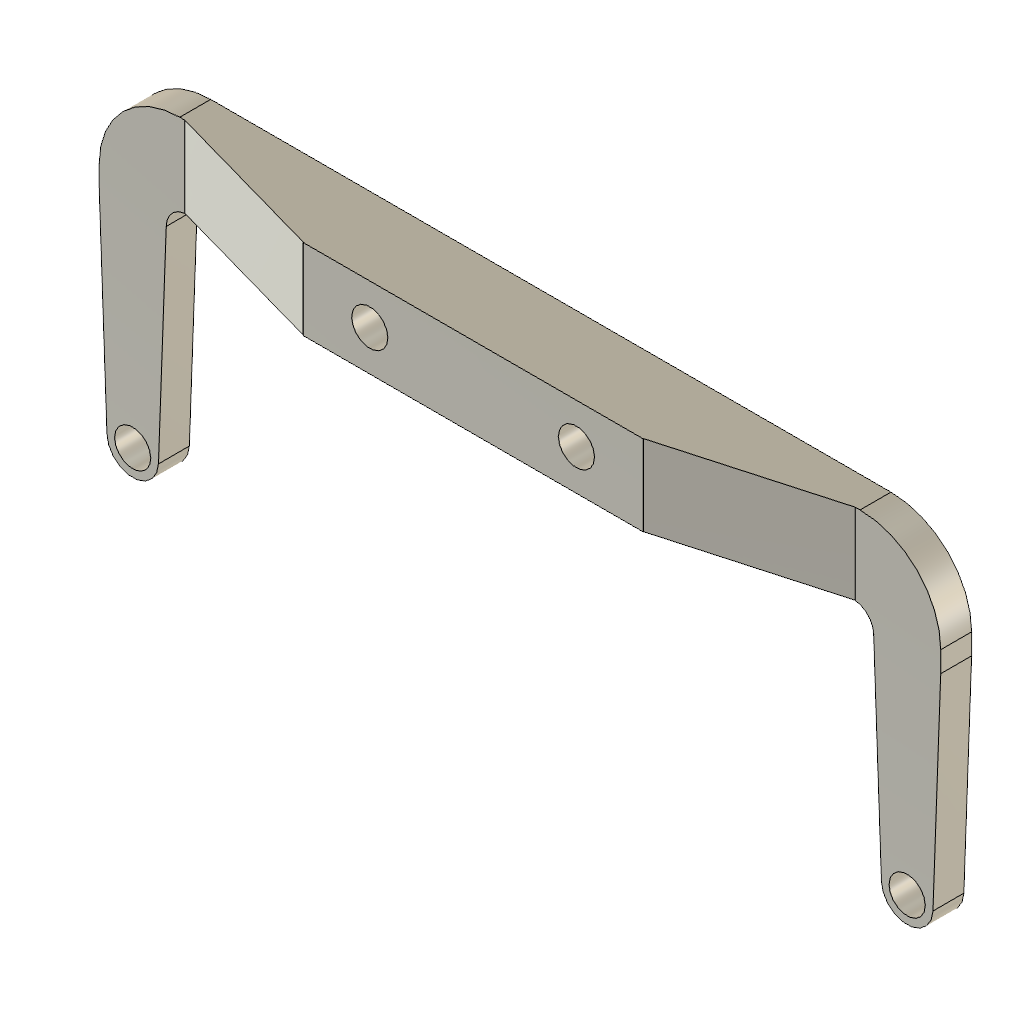
Eye Holder native (Autodesk Fusion 360 design; units mm, degrees)
part number: 2026-10-13-22-14-58-010
Autodesk Fusion 360 part; units mm, degrees
ref_plane "WorkPlane1" through (0, -1.2, 0) normal (0, 1, 0) x (0, 0, 1)
sketch "Plate" plane through (0, -1.2, 0) normal (0, 1, 0) x (1, 0, 0)
  line L0 (70.4366, -30.0122) -> (4.5629, -30.0122)
  arc A0 (-3.25, -22.1993) -> (4.5629, -30.0122) centre (4.5629, -22.1993) ccw
  line L1 (-3.25, -22.1993) -> (-3.25, -20.1993)
  line L2 (-3.25, -20.1993) -> (-2.4983, 0.0925)
  arc A1 (2.4983, 0.0925) -> (-2.4983, 0.0925) centre (0, 0) ccw
  line L3 (2.4983, 0.0925) -> (3.25, -20.1993)
  arc A2 (3.25, -20.1993) -> (5.2502, -22.1993) centre (5.2502, -20.1991) ccw
  line L4 (5.2502, -22.1993) -> (69.7495, -22.1993)
  arc A3 (69.7495, -22.1993) -> (71.7497, -20.2077) centre (69.7495, -20.1991) ccw
  line L5 (71.7497, -20.2077) -> (72.5017, 0.092)
  arc A4 (77.4983, 0.092) -> (72.5017, 0.092) centre (75, -0.0005) ccw
  line L6 (77.4983, 0.092) -> (78.2495, -20.187)
  line L7 (78.2495, -20.187) -> (78.2495, -22.1993)
  arc A5 (70.4366, -30.0122) -> (78.2495, -22.1993) centre (70.4366, -22.1993) ccw
  dimension "d33" = 7.8129
  dimension "d34" = 2.5
  dimension "d35" = 2.0002
  dimension "d36" = 4.5629
  dimension "d37" = 22.1993
  dimension "d38" = 5.2502
  dimension "d39" = 20.1991
  dimension "d40" = 69.7495
  dimension "d41" = 75
  dimension "d42" = 0.0005
  dimension "d43" = 70.4366
  dimension "d44" = 20.1993
  dimension "d45" = 2.4983
  dimension "d46" = 71.7497
  dimension "d47" = 77.4983
  constraint horizontal L0
  constraint vertical L1
  constraint horizontal L4
  constraint vertical L7
  constraint tangent L0 A5
  constraint tangent L0 A0
  constraint tangent A0 L1
  constraint tangent L2 A1
  constraint tangent A1 L3
  constraint tangent A2 L4
  constraint tangent L4 A3
  constraint tangent L5 A4
  constraint tangent A4 L6
  constraint tangent L7 A5
  constraint coincident A1.centre origin
  constraint equal A2 A3
  constraint equal A1 A4
  constraint equal A0 A5
  measures "d33" radius of A0
  measures "d34" radius of A1
  measures "d35" radius of A2
  measures "d36" horizontal distance of A1.centre A0.centre
  measures "d37" vertical distance of A1.centre A0.centre
  measures "d38" horizontal distance of A1.centre A2.centre
  measures "d39" vertical distance of A1.centre A2.centre
  measures "d40" horizontal distance of A1.centre A3.centre
  measures "d41" horizontal distance of A1.centre A4.centre
  measures "d42" vertical distance of A1.centre A4.centre
  measures "d43" horizontal distance of A1.centre A5.centre
  measures "d44" vertical distance of A1.centre L1.end
  measures "d45" horizontal distance of A1.centre A1.start
  measures "d46" horizontal distance of A1.centre A3.end
  measures "d47" horizontal distance of A1.centre A4.start
extrude "Plate (1)" add sketch "Plate" along normal mid plane 3
ref_plane "WorkPlane2" through (0, -4.7161, 0) normal (0, 1, 0) x (0, 0, 1)
sketch "Bar" plane through (0, -4.7161, 0) normal (0, 1, 0) x (1, 0, 0)
  arc A0 (5.0314, -22.1873) -> (5.2505, -22.1993) centre (5.2505, -20.1932) ccw
  line L0 (5.2505, -22.1993) -> (69.7496, -22.1993)
  arc A1 (69.7496, -22.1993) -> (69.9682, -22.1873) centre (69.7496, -20.2016) ccw
  line L1 (69.9682, -22.1873) -> (69.9682, -30.0122)
  line L2 (69.9682, -30.0122) -> (5.0314, -30.0122)
  line L3 (5.0314, -30.0122) -> (5.0314, -22.1873)
  dimension "d48" = 2.0061
  dimension "d49" = 1.9977
  dimension "d50" = 5.2505
  dimension "d51" = 20.1932
  dimension "d52" = 69.7496
  dimension "d53" = 5.0314
  dimension "d54" = 69.9682
  dimension "d55" = 30.0122
  constraint horizontal L0
  constraint vertical L1
  constraint horizontal L2
  constraint vertical L3
  constraint tangent A0 L0
  constraint tangent L0 A1
  measures "d48" radius of A0
  measures "d49" radius of A1
  measures "d50" horizontal distance of origin A0.centre
  measures "d51" vertical distance of origin A0.centre
  measures "d52" horizontal distance of origin A1.centre
  measures "d53" horizontal distance of origin A0.start
  measures "d54" horizontal distance of origin A1.end
  measures "d55" vertical distance of origin L1.end
extrude "Bar (1)" add sketch "Bar" along normal mid plane 5.0322
ref_plane "WorkPlane3" through (0, 0, 25.5061) normal (0, 0, 1) x (1, 0, 0)
sketch "Bar taper L" plane through (0, 0, 25.5061) normal (0, 0, 1) x (1, 0, 0)
  line L0 (5.0314, -2.7) -> (21.0314, -7.2)
  line L1 (21.0314, -7.2) -> (21.0314, -8.2322)
  line L2 (21.0314, -8.2322) -> (4, -8.2322)
  line L3 (4, -8.2322) -> (4, -2.7)
  line L4 (4, -2.7) -> (5.0314, -2.7)
  dimension "d56" = 5.0314
  dimension "d57" = 2.7
  dimension "d58" = 21.0314
  dimension "d59" = 7.2
  dimension "d60" = 8.2322
  dimension "d61" = 4
  constraint vertical L1
  constraint horizontal L2
  constraint vertical L3
  constraint horizontal L4
  measures "d56" horizontal distance of origin L0.start
  measures "d57" vertical distance of origin L0.start
  measures "d58" horizontal distance of origin L0.end
  measures "d59" vertical distance of origin L0.end
  measures "d60" vertical distance of origin L1.end
  measures "d61" horizontal distance of origin L2.end
extrude "Bar taper L (1)" cut sketch "Bar taper L" along normal mid plane 11.0122
ref_plane "WorkPlane4" through (0, 0, 25.5061) normal (0, 0, 1) x (1, 0, 0)
sketch "Bar taper R" plane through (0, 0, 25.5061) normal (0, 0, 1) x (1, 0, 0)
  line L0 (69.9682, -2.7) -> (71, -2.7)
  line L1 (71, -2.7) -> (71, -8.2322)
  line L2 (71, -8.2322) -> (53.9682, -8.2322)
  line L3 (53.9682, -8.2322) -> (53.9682, -7.2)
  line L4 (53.9682, -7.2) -> (69.9682, -2.7)
  dimension "d62" = 69.9682
  dimension "d63" = 2.7
  dimension "d64" = 71
  dimension "d65" = 8.2322
  dimension "d66" = 53.9682
  dimension "d67" = 7.2
  constraint horizontal L0
  constraint vertical L1
  constraint horizontal L2
  constraint vertical L3
  measures "d62" horizontal distance of origin L0.start
  measures "d63" vertical distance of origin L0.start
  measures "d64" horizontal distance of origin L0.end
  measures "d65" vertical distance of origin L1.end
  measures "d66" horizontal distance of origin L2.end
  measures "d67" vertical distance of origin L3.end
extrude "Bar taper R (1)" cut sketch "Bar taper R" along normal mid plane 11.0122
ref_plane "WorkPlane5" through (0, -3.4661, 0) normal (0, 1, 0) x (0, 0, 1)
sketch "Top hole L" plane through (0, -3.4661, 0) normal (0, 1, 0) x (1, 0, 0)
  circle A0 centre (27.4936, -26.1058) radius 1.75
  dimension "d68" = 3.5
  dimension "d69" = 27.4936
  dimension "d70" = 26.1058
  measures "d68" diameter of A0
  measures "d69" horizontal distance of origin A0.centre
  measures "d70" vertical distance of origin A0.centre
extrude "Top hole L (1)" cut sketch "Top hole L" along normal mid plane 7.5322
ref_plane "WorkPlane6" through (0, -3.4661, 0) normal (0, 1, 0) x (0, 0, 1)
sketch "Top hole R" plane through (0, -3.4661, 0) normal (0, 1, 0) x (1, 0, 0)
  circle A0 centre (47.5059, -26.1058) radius 1.75
  dimension "d71" = 3.5
  dimension "d72" = 47.5059
  dimension "d73" = 26.1058
  measures "d71" diameter of A0
  measures "d72" horizontal distance of origin A0.centre
  measures "d73" vertical distance of origin A0.centre
extrude "Top hole R (1)" cut sketch "Top hole R" along normal mid plane 7.5322
ref_plane "WorkPlane7" through (0, -1.2, 0) normal (0, 1, 0) x (0, 0, 1)
sketch "Pivot hole L" plane through (0, -1.2, 0) normal (0, 1, 0) x (1, 0, 0)
  circle A0 centre (0, 0) radius 1.75
  dimension "d74" = 3.5
  constraint coincident A0.centre origin
  measures "d74" diameter of A0
extrude "Pivot hole L (1)" cut sketch "Pivot hole L" along normal mid plane 3
ref_plane "WorkPlane8" through (0, -1.2, 0) normal (0, 1, 0) x (0, 0, 1)
sketch "Pivot hole R" plane through (0, -1.2, 0) normal (0, 1, 0) x (1, 0, 0)
  circle A0 centre (74.9995, 0) radius 1.75
  dimension "d75" = 3.5
  dimension "d76" = 74.9995
  constraint horizontal origin A0.centre
  measures "d75" diameter of A0
  measures "d76" horizontal distance of origin A0.centre
extrude "Pivot hole R (1)" cut sketch "Pivot hole R" along normal mid plane 3
named bodies: "Eye Holder native"
